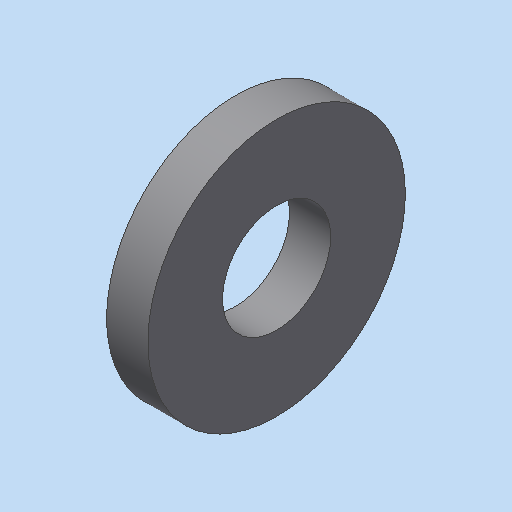
# Autodesk Inventor part: Scheibe__DIN_7349___10_5
Saved by Autodesk Inventor 2023.3 (Build 273359000, 359)
## iProperties
Shininess: 64.0
Length Units: 11269
Angle Units: 11279
Time Units: 11290
Mass Units: 11283
Length Display Precision: 3
Angle Display Precision: 2
Compacted: True
Part Number: Scheibe__DIN_7349___10_5
Document SubType Name: Modeling
Created: 2004-04-25
Description: =<RBPARTNOTITLE2>
Vendor: NORM8
Designer: C.Fischer
Manufacturer: Standard
Standards Organization: Custom
Density: 7.85 g/cm^3
Material: xStahl_AnP_Dummymaterial
Mass: 12.6945 g
Surface Area: 12.5467 cm^2
Volume: 1.61713 cm^3
Appearance: RGB(178,178,178)
Density: 0.0
Volumn: 0.0
Area: 0.0
PropertySet Name: Model Information
Control State: 0
Master: False
Checked Out: False
CNS_NB: Scheibe  DIN 7349 - 10.5
CNS_NN: DIN 7349
CNS_NT: Scheibe fuer Schraube mit schwerer Spannhuelse
CNS_NBSYN: Scheibe  DIN 7349 - $NENN.
CNS_LINA: Scheibe  DIN 7349 - 10.5
CNS_NENN: 10.5
CNS_D: 10.000
CNS_DA: 10.500
CNS_DW: 25.000
CNS_H: 4.000
CNS_SPH: 18.000
CNS_KT: X
PSOL_IDENT_0: {C:\partsolutions\data\23d-libs\bosch_bamberg\zubehoer\scheiben\din_7349.prj},144 {VTYP=3D},{NB=Sche
PSOL_IDENT_1: ibe  DIN 7349 - 10.5},{NN=DIN 7349},{DATE=26.11.2003},{GEOMDATE=26.11.2003},{VERSION=v1},{LINEID=60}
PSOL_IDENT_2: ,{LINESUBID=-1},{WBVAR=}  {NB=Scheibe  DIN 7349 - 10.5},{LINA=Scheibe  DIN 7349 - 10.5},{KT=X},{IDNR
PSOL_IDENT_3: =},{NENN=10.5},{D=10.000},{DA=10.500},{DW=25.000},{H=4.000},{SPH=18.000}
RBPARTNOTITLE2: Scheibe fuer Schraube mit schwerer Spannhuelse
RBPARTMADEOF: DIN 7349 - 10.5
Title: Scheibe  DIN 7349 - 10.5
Author: C.Fischer
Keywords: =<RBPARTMADEOF>
Revision Number: 01
Autodesk Inventor part; units mm, degrees
sketch "Sketch_1" plane through (0, 0, 0) normal (0, 0, 1) x (1, 0, 0)
  line L0 (4, 0) -> (-8, 0)
  line L1 (0, 12.5) -> (0, 5.25)
  line L2 (0, 5.25) -> (4, 5.25)
  line L3 (4, 5.25) -> (4, 12.5)
  line L4 (4, 12.5) -> (0, 12.5)
  constraints: 10 end point
revolve "Revolution1" add sketch "Sketch_1" angle 360 about axis through (4, 0, 0) along (-1, 0, 0)
ref_plane "IP1_XY" through (0, 0, 0) normal (1, 0, 0) x (0, 0, -1)
ref_plane "IP1_YZ" through (0, 0, 0) normal (0, 0, -1) x (0, 1, 0)
ref_plane "IP2_XY" through (4, 0, 0) normal (1, 0, 0) x (0, 0, -1)
ref_plane "IP2_YZ" through (4, 0, 0) normal (0, 0, -1) x (0, 1, 0)
